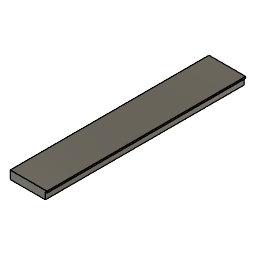
Walls - Baseboard (Autodesk Fusion 360 design; units mm, degrees)
Autodesk Fusion 360 part; units mm, degrees
sketch "Sketch1" plane through (0, 0, 0) normal (0, 1, 0) x (1, 0, 0)
  line L0 (0, 0) -> (44.5, 0)
  line L1 (44.5, 0) -> (44.5, -10)
  line L2 (44.5, -10) -> (0, -10)
  line L3 (0, -10) -> (0, 0)
  line L4 (44.5, 0) -> (42.5, 0)
  line L5 (42.5, 0) -> (42.5, -8.2)
  line L6 (42.5, -8.2) -> (44.5, -8.2)
  line L7 (44.5, -8.2) -> (44.5, 0)
  dimension "d1" = 44.5
  dimension "d2" = 10
  dimension "d3" = 2
  dimension "d4" = 8.2
  constraint horizontal L0
  constraint vertical L1
  constraint horizontal L2
  constraint vertical L3
  constraint coincident L0.start L3.end
  constraint horizontal L4
  constraint vertical L5
  constraint horizontal L6
  constraint vertical L7
  measures "d1" distance of L0.start L0.end
  measures "d2" distance of L0.start L2.end
  measures "d3" distance of L0.end L4.end
  measures "d4" distance of L0.end L6.end
extrude "Extrude1" add sketch "Sketch1" along normal blind 240 contours L0 L1 L2 L3 L5 L6
